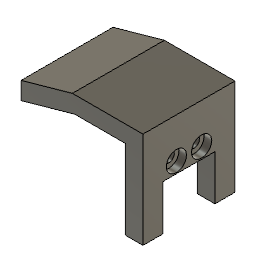
Door Base Handels (Autodesk Fusion 360 archive; units mm, degrees)
design "Handle Arm"
part number: 2026-03-16-23-26-48-181
Autodesk Fusion 360 part; units mm, degrees
sketch "Sketch2" plane through (0, 0, 0) normal (0, 1, 0) x (1, 0, 0)
  line L0 (53, 2.4058) -> (53, -35.9342)
  line L1 (53, -35.9342) -> (24.9488, -35.9342)
  line L2 (4.5, -30.1942) -> (24.9488, -35.9342)
  line L3 (4.5, -30.1942) -> (4.5, -23.1942)
  line L4 (4.5, -23.1942) -> (25.875, -29.1942)
  line L5 (25.875, -29.1942) -> (46, -29.1942)
  line L6 (46, -29.1942) -> (46, 2.4058)
  line L7 (46, 2.4058) -> (53, 2.4058)
  dimension "d4" = 7
  dimension "d7" = 48.5
  dimension "d8" = 6.7395
  dimension "d9" = 7
  dimension "d10" = 6
  dimension "d11" = 31.6
  dimension "d31" = 6.74
  constraint vertical L3
  constraint horizontal L5
  constraint perpendicular L5 L6
  constraint perpendicular L6 L7
  measures "d4" distance of L2.start L3.end
  measures "d7" distance of L0 L3
  measures "d8" distance of L2 L4
  measures "d9" distance of L0 L6
  measures "d10" distance of L3.end L5
  measures "d11" distance of L5.end L6.end
  measures "d31" distance of L1 L5
extrude "Extrude1" add sketch "Sketch2" along normal blind 36.6
sketch "Sketch4" plane through (53, 0, 0) normal (1, 0, 0) x (0, 1, 0)
  line L0 (0, 35.9342) -> (0, -2.4058)
  line L1 (0, -2.4058) -> (36.6, -2.4058)
  line L2 (36.6, -2.4058) -> (36.6, 35.9342)
  line L3 (36.6, 35.9342) -> (0, 35.9342)
  line L4 (8, -2.4058) -> (28.6, -2.4058)
  line L5 (28.6, -2.4058) -> (28.6, 15.5942)
  line L6 (28.6, 15.5942) -> (8, 15.5942)
  line L7 (8, 15.5942) -> (8, -2.4058)
  dimension "d15" = 20.6
  dimension "d16" = 18
  constraint horizontal L4
  constraint vertical L5
  constraint horizontal L6
  constraint vertical L7
  constraint coincident L1 L4.start
  constraint midpoint L1 L4
  measures "d15" distance of L4.start L4.end
  measures "d16" distance of L4.start L6.end
extrude "Extrude2" cut sketch "Sketch4" against normal up to surface (7 mm away) contours L1 L4 L5 L6 L7
hole "Hole1" at (53, 13.3, 20.0442) direction (-1, 0, 0) diameter 4.3 end up to surface (7 mm away) counterbore diameter 8 counterbore depth 3
hole "Hole2" at (53, 23.3, 20.0442) direction (-1, 0, 0) diameter 4.3 end up to surface (7 mm away) counterbore diameter 8 counterbore depth 3
equation "d11 = 25 mm + 6.6 mm"

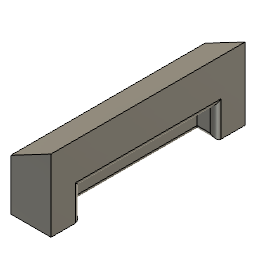
design "Door Base Handels"
part number: 2026-03-16-20-29-31-523
Autodesk Fusion 360 part; units mm, degrees
sketch "Sketch1" plane through (0, 0, 0) normal (1, 0, 0) x (0, 1, 0)
  line L0 (-18.5, 107) -> (18.1, 107)
  line L1 (-18.5, 93.4) -> (-18.5, 107)
  line L2 (18.1, 93.4) -> (-18.5, 93.4)
  line L3 (-12.9, 99) -> (12.5, 99)
  line L4 (-12.9, 93.4) -> (-12.9, 99)
  line L5 (12.5, 99) -> (12.5, 93.4)
  line L6 (18.1, 107) -> (18.1, 93.4)
  dimension "d21" = 13.6
  dimension "d22" = 5.6
  dimension "d23" = 5.6
  dimension "d24" = 36.6
  dimension "d25" = 25.4
  dimension "d26" = 5.6
  dimension "d27" = 5.6
  constraint horizontal L0
  constraint vertical L6
  constraint horizontal L2
  constraint vertical L1
  constraint horizontal L3
  constraint vertical L5
  constraint vertical L4
  measures "d21" distance of L0.start L1.start
  measures "d22" distance of L3.start L4.start
  measures "d23" distance of L3.end L5.end
  measures "d24" distance of L0.start L0.end
  measures "d25" distance of L4 L5
  measures "d26" distance of L1 L4
  measures "d27" distance of L5 L6
extrude "Extrude2" add sketch "Sketch1" along normal blind 7.6
extrude "Extrude3" cut sketch "Sketch1" against normal blind 3.5 from surface at 7.6 contours L2 L3 L4 L5
fillet "Fillet2" radius 1 6 edges at (7.6, -0.2, 99) (7.6, -12.9, 96.2) (4.1, -0.2, 93.4) (7.6, 12.5, 96.2) (5.85, 12.5, 93.4) (5.85, -12.9, 93.4)
sketch "Sketch3" plane through (0, 18.1, 0) normal (0, 1, 0) x (-1, 0, 0)
  line L0 (0, 93.4) -> (0, 107)
  line L1 (0, 107) -> (-7.6, 107)
  line L2 (-7.6, 107) -> (-7.6, 93.4)
  line L3 (-7.6, 93.4) -> (0, 93.4)
  line L4 (0, 103) -> (-7.6, 107)
  point P0 (0, 103)
  constraint coincident L0 P0
  constraint coincident P0 L4.start
  constraint coincident L1.end L2.start
extrude "Extrude4" cut sketch "Sketch3" against normal up to surface (36.6 mm away) contours L0 L1 L4
